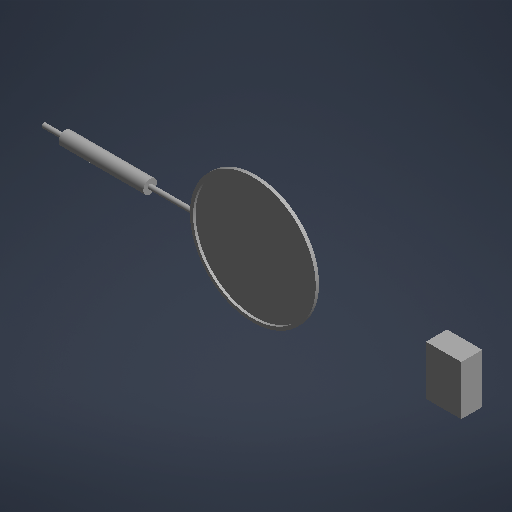
# Autodesk Inventor part: s1101mfa1700
Saved by Autodesk Inventor 2026.4 (Build 304435000, 435)
## iProperties
Part Number: s1101mfa1700
Material: Genérico
Document SubType Name: Modelagem
Designer: User
Appearance: Padrão
Author: User
Autodesk Inventor part; units mm, degrees
ref_plane "Plano YZ" through (0, 0, 0) normal (1, 0, 0) x (0, 1, 0)
ref_plane "Plano XZ" through (0, 0, 0) normal (0, 1, 0) x (-1, 0, 0)
ref_plane "Plano XY" through (0, 0, 0) normal (0, 0, 1) x (1, 0, 0)
sketch "Esboço1" plane through (0, 0, 0) normal (0, 0, 1) x (1, 0, 0)
  circle A0 centre (0, 0) radius 44.45
  circle A1 centre (0, 0) radius 42.165
  constraints: 2 centre point
extrude "Extrusão1" add sketch "Esboço1" along normal blind 2.38
sketch "Esboço2" plane through (0, 0, 0) normal (0, 0, 1) x (1, 0, 0)
  circle A0 centre (0, 0) radius 42.165
  constraints: 1 centre point
extrude "Extrusão2" add sketch "Esboço2" along normal blind 0.6
sketch "Esboço3" plane through (0, 0, 0) normal (0, 1, 0) x (-1, 0, 0)
  line L0 (44, 0) -> (150, 0)
  line L1 (150, 0) -> (150, 1.59)
  line L2 (150, 1.59) -> (44, 1.59)
  line L3 (44, 1.59) -> (44, 0)
  constraints: 8 end point
revolve "Revolução1" add sketch "Esboço3" angle 360 about axis through (-44, 0, 0) along (-1, 0, 0)
sketch "Esboço4" plane through (0, 0, 0) normal (0, 1, 0) x (-1, 0, 0)
  line L0 (75, 0) -> (135, 0)
  line L1 (135, 0) -> (135, 4.765)
  line L2 (135, 4.765) -> (75, 4.765)
  line L3 (75, 4.765) -> (75, 0)
  constraints: 8 end point
revolve "Revolução2" add sketch "Esboço4" angle 360 about axis through (-75, 0, 0) along (-1, 0, 0)
sketch "Esboço5" plane through (0, 0, 0) normal (0, 0, 1) x (1, 0, 0)
  line L0 (135, -17.5) -> (160, -17.5)
  line L1 (160, -17.5) -> (160, 17.5)
  line L2 (160, 17.5) -> (135, 17.5)
  line L3 (135, 17.5) -> (135, -17.5)
  line L4 (135, -17.5) -> (160, 17.5) construction
  line L5 (160, -17.5) -> (135, 17.5) construction
  point P0 (147.5, 0)
  constraints: 12 end point, 2 midpoint, 2 parallel, 1 horizontal, 1 perpendicular
extrude "Extrusão3" add sketch "Esboço5" along normal blind 15
